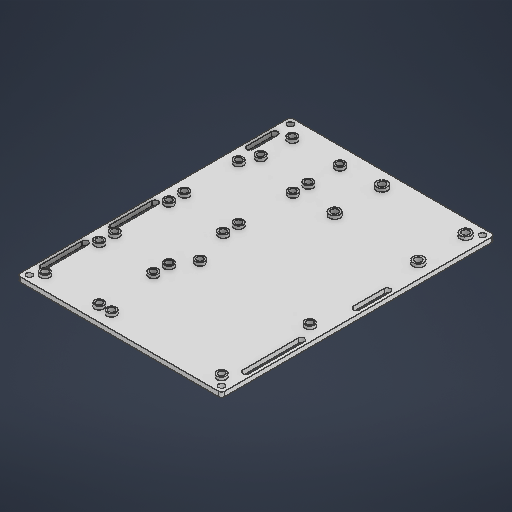
# Autodesk Inventor part: a
Saved by Autodesk Inventor 2026.2 (Build 302298010, 298A)
## iProperties
Created: 2026-03-20
Part Number: a
Material: 일반
Document SubType Name: Modeling
Designer: work
Density: 1 g/cm^3
Appearance: 기본값
Author: work
Autodesk Inventor part; units mm, degrees
ref_plane "YZ Plane" through (0, 0, 0) normal (1, 0, 0) x (0, 1, 0)
ref_plane "XZ Plane" through (0, 0, 0) normal (0, 1, 0) x (-1, 0, 0)
ref_plane "XY Plane" through (0, 0, 0) normal (0, 0, 1) x (1, 0, 0)
sketch "스케치1" plane through (0, 0, 0) normal (0, 1, 0) x (-1, 0, 0)
  line L0 (0, 0) -> (124, 0) construction
  line L1 (124, 0) -> (124, -168.4) construction
  line L2 (124, -168.4) -> (0, -168.4) construction
  line L3 (0, -168.4) -> (0, 0) construction
  circle A0 centre (5, -5) radius 3
  line L4 (5, -5) -> (76, -5) construction
  line L5 (76, -5) -> (76, -62) construction
  line L6 (76, -62) -> (5, -62) construction
  line L7 (5, -62) -> (5, -5) construction
  circle A1 centre (5, -62) radius 3
  circle A2 centre (76, -5) radius 3
  circle A3 centre (76, -62) radius 3
  line L8 (84, -5) -> (119, -5) construction
  line L9 (119, -5) -> (119, -40) construction
  line L10 (119, -40) -> (84, -40) construction
  line L11 (84, -40) -> (84, -5) construction
  circle A4 centre (119, -5) radius 3
  circle A5 centre (84, -5) radius 3
  circle A6 centre (84, -40) radius 3
  circle A7 centre (119, -40) radius 3
  line L12 (84, -50) -> (119, -50) construction
  line L13 (119, -50) -> (119, -85) construction
  line L14 (119, -85) -> (84, -85) construction
  line L15 (84, -85) -> (84, -50) construction
  circle A8 centre (119, -50) radius 3
  circle A9 centre (84, -50) radius 3
  circle A10 centre (84, -85) radius 3
  circle A11 centre (119, -85) radius 3
  line L16 (5, -72) -> (75, -72)
  line L17 (75, -72) -> (75, -122)
  line L18 (75, -122) -> (5, -122)
  line L19 (5, -122) -> (5, -72)
  line L20 (84, -140) -> (114.8, -140) construction
  line L21 (114.8, -140) -> (114.8, -160.4) construction
  line L22 (114.8, -160.4) -> (84, -160.4) construction
  line L23 (84, -160.4) -> (84, -140) construction
  circle A12 centre (84, -140) radius 3
  circle A13 centre (114.8, -140) radius 3
  circle A14 centre (114.8, -160.4) radius 3
  circle A15 centre (84, -160.4) radius 3
  line L24 (128, 4) -> (-4, 4)
  line L25 (-4, 4) -> (-4, -172.4)
  line L26 (-4, -172.4) -> (128, -172.4)
  line L27 (128, -172.4) -> (128, 4)
  circle A16 centre (0, 0) radius 2
  circle A17 centre (0, -168.4) radius 2
  circle A18 centre (124, -168.4) radius 2
  circle A19 centre (124, 0) radius 2
  line L28 (84, -130) -> (84, -95) construction
  circle A20 centre (84, -95) radius 3
  circle A21 centre (84, -130) radius 3
  line L29 (119, -95) -> (119, -130) construction
  line L30 (84, -95) -> (119, -95) construction
  circle A22 centre (119, -95) radius 3
  line L31 (119, -130) -> (84, -130) construction
  circle A23 centre (119, -130) radius 3
  line L32 (5, -132) -> (59, -132) construction
  line L33 (59, -132) -> (59, -162.5) construction
  line L34 (59, -162.5) -> (5, -162.5) construction
  line L35 (5, -162.5) -> (5, -132) construction
  circle A24 centre (59, -132) radius 2.25
  circle A25 centre (59, -162.5) radius 2.25
  circle A26 centre (5, -132) radius 2.25
  circle A27 centre (5, -162.5) radius 2.25
  point P0 (62, -168.4)
  dimension "d0" = 6
  dimension "d1" = 57
  dimension "d2" = 5
  dimension "d3" = 5
  dimension "d4" = 6
  dimension "d5" = 71
  dimension "d6" = 6
  dimension "d7" = 6
  dimension "d8" = 35
  dimension "d9" = 35
  dimension "d10" = 6
  dimension "d11" = 8
  dimension "d12" = 6
  dimension "d13" = 5
  dimension "d14" = 6
  dimension "d15" = 6
  dimension "d16" = 35
  dimension "d17" = 35
  dimension "d18" = 6
  dimension "d19" = 6
  dimension "d20" = 6
  dimension "d21" = 6
  dimension "d22" = 10
  dimension "d23" = 70
  dimension "d24" = 50
  dimension "d25" = 10
  dimension "d26" = 5
  dimension "d27" = 20.4
  dimension "d28" = 30.8
  dimension "d30" = 6
  dimension "d31" = 6
  dimension "d32" = 6
  dimension "d33" = 6
  dimension "d34" = 5
  dimension "d36" = 4
  dimension "d37" = 4
  dimension "d38" = 4
  dimension "d39" = 4
  dimension "d40" = 4
  dimension "d41" = 4
  dimension "d42" = 4
  dimension "d43" = 4
  dimension "d74" = 35
  dimension "d75" = 35
  dimension "d76" = 6
  dimension "d77" = 6
  dimension "d78" = 6
  dimension "d79" = 6
  dimension "d80" = 10
  dimension "d81" = 10
  dimension "d82" = 8
  dimension "d83" = 30.5
  dimension "d84" = 54
  dimension "d85" = 10
  dimension "d86" = 5
  dimension "d87" = 4.5
  dimension "d88" = 4.5
  dimension "d89" = 4.5
  dimension "d90" = 4.5
  constraints: 72 end point, 28 centre point, 24 coincident, 18 parallel, 9 horizontal, 9 perpendicular, 3 collinear, 1 midpoint
  measures "d0" diameter of A0
  measures "d1" distance of L6.end L4.start
  measures "d2" distance from line of L3 L4.start
  measures "d3" distance between parallel lines of L0 L4
  measures "d4" diameter of A1
  measures "d5" distance of L4.start L4.end
  measures "d6" diameter of A2
  measures "d7" diameter of A3
  measures "d8" distance of L9.end L10.end
  measures "d9" distance of L8.end L9.end
  measures "d10" diameter of A4
  measures "d11" distance of L4.end L8.start
  measures "d12" diameter of A5
  measures "d13" distance between parallel lines of L0 L8
  measures "d14" diameter of A6
  measures "d15" diameter of A7
  measures "d16" distance of L13.end L15.start
  measures "d17" distance of L13.start L13.end
  measures "d18" diameter of A8
  measures "d19" diameter of A9
  measures "d20" diameter of A10
  measures "d21" diameter of A11
  measures "d22" distance from line of L15.end L10
  measures "d23" distance of L17.end L18.end
  measures "d24" distance of L16.end L17.end
  measures "d25" distance between parallel lines of L6 L16
  measures "d26" distance between parallel lines of L3 L19
  measures "d27" distance of L20.end L21.end
  measures "d28" distance of L20.start L20.end
  measures "d30" diameter of A12
  measures "d31" diameter of A13
  measures "d32" diameter of A14
  measures "d33" diameter of A15
  measures "d34" distance between parallel lines of L1 L13
  measures "d36" distance from line of L24 L0.start
  measures "d37" distance between parallel lines of L25 L3
  measures "d38" diameter of A16
  measures "d39" diameter of A17
  measures "d40" distance from line of L27 L1.end
  measures "d41" distance from line of L26 L1.end
  measures "d42" diameter of A18
  measures "d43" diameter of A19
  measures "d74" distance of L31.start L28.start
  measures "d75" distance of L29.start L31.start
  measures "d76" diameter of A22
  measures "d77" diameter of A20
  measures "d78" diameter of A21
  measures "d79" diameter of A23
  measures "d80" distance of A20.centre L15.start
  measures "d81" distance of L20.start L28.start
  measures "d82" distance from line of L22.end L2
  measures "d83" distance of L34.end L32.start
  measures "d84" distance of L32.start L32.end
  measures "d85" distance of L18.end L32.start
  measures "d86" distance between parallel lines of L3 L35
  measures "d87" diameter of A24
  measures "d88" diameter of A25
  measures "d89" diameter of A26
  measures "d90" diameter of A27
extrude "돌출1" add sketch "스케치1" along normal blind 3 contours A0 | A1 | A2 | A3 | A4 | A5 | A6 | A7 | A8 | A9 | A10 | A11 | L16 L17 L18 L19 | A12 | A13 | A14 | A15 | L27 L26 L25 L24 | A20 | A21 | A22 | A23
extrude "돌출2" add sketch "스케치1" along normal blind 5 contours A0 | A1 | A2 | A3 | A4 | A5 | A6 | A7 | A8 | A9 | A10 | A11 | A12 | A13 | A14 | A15 | A20 | A21 | A22 | A23
sketch "스케치2" plane through (-5, 5, -5) normal (0, 1, 0) x (1, 0, 0)
  line L0 (9, -9) -> (9, 167.4) projected
  line L1 (9, 167.4) -> (-123, 167.4) projected
  line L2 (-123, 167.4) -> (-123, -9) projected
  line L3 (-123, -9) -> (9, -9) projected
  circle A0 centre (-119, 163.4) radius 2 projected
  circle A1 centre (5, 163.4) radius 2 projected
  circle A2 centre (-119, -5) radius 2 projected
  circle A3 centre (5, -5) radius 2 projected
  circle A4 centre (-114, 90) radius 3 projected
  circle A5 centre (-71, 0) radius 3 projected
  circle A6 centre (-114, 45) radius 3 projected
  circle A7 centre (-79, 80) radius 3 projected
  circle A8 centre (-79, 155.4) radius 3 projected
  circle A9 centre (-79, 135) radius 3 projected
  circle A10 centre (-71, 57) radius 3 projected
  circle A11 centre (-114, 35) radius 3 projected
  circle A12 centre (0, 57) radius 3 projected
  circle A13 centre (-79, 90) radius 3 projected
  circle A14 centre (-114, 125) radius 3 projected
  circle A15 centre (-79, 0) radius 3 projected
  circle A16 centre (-79, 35) radius 3 projected
  circle A17 centre (-114, 80) radius 3 projected
  circle A18 centre (-109.8, 155.4) radius 3 projected
  circle A19 centre (-109.8, 135) radius 3 projected
  circle A20 centre (-79, 45) radius 3 projected
  circle A21 centre (-114, 0) radius 3 projected
  circle A22 centre (0, 0) radius 3 projected
  circle A23 centre (-79, 125) radius 3 projected
  line L4 (9, -9) -> (9, 167.4) projected
  line L5 (9, 167.4) -> (-123, 167.4) projected
  line L6 (-123, 167.4) -> (-123, -9) projected
  line L7 (-123, -9) -> (9, -9) projected
  circle A24 centre (0, 157.5) radius 2.25 projected
  circle A25 centre (-54, 157.5) radius 2.25 projected
  circle A26 centre (-119, 163.4) radius 2 projected
  circle A27 centre (5, 163.4) radius 2 projected
  circle A28 centre (-54, 127) radius 2.25 projected
  circle A29 centre (0, 127) radius 2.25 projected
  circle A30 centre (-119, -5) radius 2 projected
  circle A31 centre (5, -5) radius 2 projected
  constraints: 4 coincident
hole "구멍1" at (-76, 5, -5) at (-84, 5, -5) at (-5, 5, -5) at (-5, 5, -62) at (-76, 5, -62) at (-84, 5, -50) at (-84, 5, -40) at (-119, 5, -5) at (-119, 5, -40) at (-119, 5, -50) at (-119, 5, -85) at (-84, 5, -85) at (-84, 5, -140) at (-114.8, 5, -140) at (-114.8, 5, -160.4) at (-84, 5, -160.4) at (-84, 5, -95) at (-119, 5, -95) at (-119, 5, -130) at (-84, 5, -130) direction (0, -1, 0) diameter 4 end through all
fillet "모깎기1" radius 2 4 edges at (4, 1.5, -172.4) (-128, 1.5, -172.4) (-128, 1.5, 4) (4, 1.5, 4)
sketch "스케치3" plane through (0, 3, 0) normal (0, 1, 0) x (1, 0, 0)
  arc A0 (2, -4) -> (4, -2) centre (2, -2) ccw projected
  line L0 (4, -2) -> (4, 170.4) projected
  arc A1 (4, 170.4) -> (2, 172.4) centre (2, 170.4) ccw projected
  line L1 (2, 172.4) -> (-126, 172.4) projected
  arc A2 (-126, 172.4) -> (-128, 170.4) centre (-126, 170.4) ccw projected
  line L2 (-128, 170.4) -> (-128, -2) projected
  arc A3 (-128, -2) -> (-126, -4) centre (-126, -2) ccw projected
  line L3 (-126, -4) -> (2, -4) projected
  circle A4 centre (-124, 168.4) radius 2 projected
  circle A5 centre (0, 168.4) radius 2 projected
  circle A6 centre (-124, 0) radius 2 projected
  circle A7 centre (0, 0) radius 2 projected
  circle A8 centre (-5, 5) radius 2 projected
  circle A9 centre (-5, 62) radius 2 projected
  line L4 (-5, 5) -> (-5, 62) construction
  line L5 (-124, 9) -> (-124, 36) construction
  line L6 (-122, 9) -> (-122, 36)
  line L7 (-126, 36) -> (-126, 9)
  arc A10 (-126, 9) -> (-122, 9) centre (-124, 9) ccw
  arc A11 (-122, 36) -> (-126, 36) centre (-124, 36) ccw
  line L8 (-119, 40) -> (-119, 50) construction
  line L9 (-119, 45) -> (-128, 45) construction
  line L10 (-124, 81) -> (-124, 54) construction
  line L11 (-122, 81) -> (-122, 54)
  line L12 (-126, 54) -> (-126, 81)
  arc A12 (-122, 81) -> (-126, 81) centre (-124, 81) ccw
  arc A13 (-126, 54) -> (-122, 54) centre (-124, 54) ccw
  line L13 (-114.8, 140) -> (-114.8, 160.4) construction
  line L14 (-114.8, 150.2) -> (-128, 150.2) construction
  line L15 (-124, 142.2) -> (-124, 158.2) construction
  line L16 (-122, 142.2) -> (-122, 158.2)
  line L17 (-126, 158.2) -> (-126, 142.2)
  arc A14 (-126, 142.2) -> (-122, 142.2) centre (-124, 142.2) ccw
  arc A15 (-122, 158.2) -> (-126, 158.2) centre (-124, 158.2) ccw
  line L18 (-5, 33.5) -> (4, 33.5) construction
  line L19 (0, 15.5) -> (0, 51.5) construction
  line L20 (2, 15.5) -> (2, 51.5)
  line L21 (-2, 51.5) -> (-2, 15.5)
  arc A16 (-2, 15.5) -> (2, 15.5) centre (0, 15.5) ccw
  arc A17 (2, 51.5) -> (-2, 51.5) centre (0, 51.5) ccw
  line L22 (-5, 97) -> (4, 97) construction
  line L23 (0, 87) -> (0, 107) construction
  line L24 (2, 87) -> (2, 107)
  line L25 (-2, 107) -> (-2, 87)
  arc A18 (-2, 87) -> (2, 87) centre (0, 87) ccw
  arc A19 (2, 107) -> (-2, 107) centre (0, 107) ccw
  point P0 (-124, 22.5)
  point P1 (-124, 67.5)
  point P2 (-124, 150.2)
  point P3 (0, 33.5)
  point P4 (0, 97)
  dimension "d58" = 4
  dimension "d60" = 4
  dimension "d61" = 4
  dimension "d62" = 8
  dimension "d63" = 4
  dimension "d64" = 4
  dimension "d65" = 18
  dimension "d66" = 4
  dimension "d67" = 4
  dimension "d68" = 10
  dimension "d69" = 4
  dimension "d70" = 4
  constraints: 54 end point, 20 point on circle, 16 tangent, 10 centre point, 7 midpoint, 7 perpendicular, 7 point on line, 7 symmetric about line, 4 parallel, 4 vertical, 2 other
  measures "d58" distance between parallel lines of L6 L7
  measures "d60" vertical distance of L8.start L5.end
  measures "d61" distance from line of L2 point (-124, 22.5)
  measures "d62" distance of point (-124, 150.2) L15.end
  measures "d63" diameter of A15
  measures "d64" distance from line of L2 point (-124, 150.2)
  measures "d65" distance of point (0, 33.5) L19.end
  measures "d66" diameter of A17
  measures "d67" distance from line of L0 point (0, 33.5)
  measures "d68" distance of point (0, 97) L23.end
  measures "d69" diameter of A19
  measures "d70" distance from line of L0 point (0, 97)
extrude "돌출4" cut sketch "스케치3" against normal through all contours A10 L7 A11 L6 | L11 A13 L12 A12 | A14 L17 A15 L16 | A16 L21 A17 L20 | A18 L25 A19 L24
sketch "스케치4" plane through (0, 3, 0) normal (0, 1, 0) x (1, 0, 0)
  line L0 (-126, 9) -> (-126, 36) projected
  arc A0 (-122, 36) -> (-126, 36) centre (-124, 36) ccw projected
  line L1 (-122, 36) -> (-122, 9) projected
  arc A1 (-126, 9) -> (-122, 9) centre (-124, 9) ccw projected
  line L2 (-2, 15.5) -> (-2, 51.5) projected
  arc A2 (2, 51.5) -> (-2, 51.5) centre (0, 51.5) ccw projected
  line L3 (2, 51.5) -> (2, 15.5) projected
  arc A3 (-2, 15.5) -> (2, 15.5) centre (0, 15.5) ccw projected
  arc A4 (-126, 54) -> (-122, 54) centre (-124, 54) ccw projected
  line L4 (-126, 54) -> (-126, 81) projected
  arc A5 (-122, 81) -> (-126, 81) centre (-124, 81) ccw projected
  line L5 (-122, 81) -> (-122, 54) projected
  line L6 (-2, 87) -> (-2, 107) projected
  arc A6 (2, 107) -> (-2, 107) centre (0, 107) ccw projected
  line L7 (2, 107) -> (2, 87) projected
  arc A7 (-2, 87) -> (2, 87) centre (0, 87) ccw projected
  line L8 (-126, 142.2) -> (-126, 158.2) projected
  arc A8 (-122, 158.2) -> (-126, 158.2) centre (-124, 158.2) ccw projected
  line L9 (-122, 158.2) -> (-122, 142.2) projected
  arc A9 (-126, 142.2) -> (-122, 142.2) centre (-124, 142.2) ccw projected
  arc A10 (2, -4) -> (4, -2) centre (2, -2) ccw projected
  line L10 (4, -2) -> (4, 170.4) projected
  arc A11 (4, 170.4) -> (2, 172.4) centre (2, 170.4) ccw projected
  line L11 (2, 172.4) -> (-126, 172.4) projected
  arc A12 (-126, 172.4) -> (-128, 170.4) centre (-126, 170.4) ccw projected
  line L12 (-128, 170.4) -> (-128, -2) projected
  arc A13 (-128, -2) -> (-126, -4) centre (-126, -2) ccw projected
  line L13 (-126, -4) -> (2, -4) projected
  circle A14 centre (-119, 95) radius 3 projected
  circle A15 centre (-76, 5) radius 3 projected
  circle A16 centre (-119, 50) radius 3 projected
  circle A17 centre (-84, 85) radius 3 projected
  circle A18 centre (-84, 160.4) radius 3 projected
  circle A19 centre (-84, 140) radius 3 projected
  circle A20 centre (-76, 62) radius 3 projected
  circle A21 centre (-119, 40) radius 3 projected
  circle A22 centre (-5, 62) radius 3 projected
  circle A23 centre (-84, 95) radius 3 projected
  circle A24 centre (-119, 130) radius 3 projected
  circle A25 centre (-84, 5) radius 3 projected
  circle A26 centre (-84, 40) radius 3 projected
  circle A27 centre (-119, 85) radius 3 projected
  circle A28 centre (-114.8, 160.4) radius 3 projected
  circle A29 centre (-114.8, 140) radius 3 projected
  circle A30 centre (-84, 50) radius 3 projected
  circle A31 centre (-119, 5) radius 3 projected
  circle A32 centre (-5, 5) radius 3 projected
  circle A33 centre (-84, 130) radius 3 projected
  circle A34 centre (-5, 162.5) radius 2.25 projected
  circle A35 centre (-59, 162.5) radius 2.25 projected
  circle A36 centre (-124, 168.4) radius 2 projected
  circle A37 centre (0, 168.4) radius 2 projected
  circle A38 centre (-59, 132) radius 2.25 projected
  circle A39 centre (-5, 132) radius 2.25 projected
  circle A40 centre (-124, 0) radius 2 projected
  circle A41 centre (0, 0) radius 2 projected
  circle A42 centre (-59, 132) radius 3.5
  circle A43 centre (-59, 162.5) radius 3.5
  circle A44 centre (-5, 132) radius 3.5
  circle A45 centre (-5, 162.5) radius 3.5
  dimension "d91" = 7
  dimension "d92" = 7
  dimension "d93" = 7
  dimension "d94" = 7
  constraints: 4 centre point, 1 coincident
  measures "d91" diameter of A42
  measures "d92" diameter of A43
  measures "d93" diameter of A44
  measures "d94" diameter of A45
extrude "돌출5" add sketch "스케치4" along normal blind 2 contours A42 | A43 | A44 | A45
